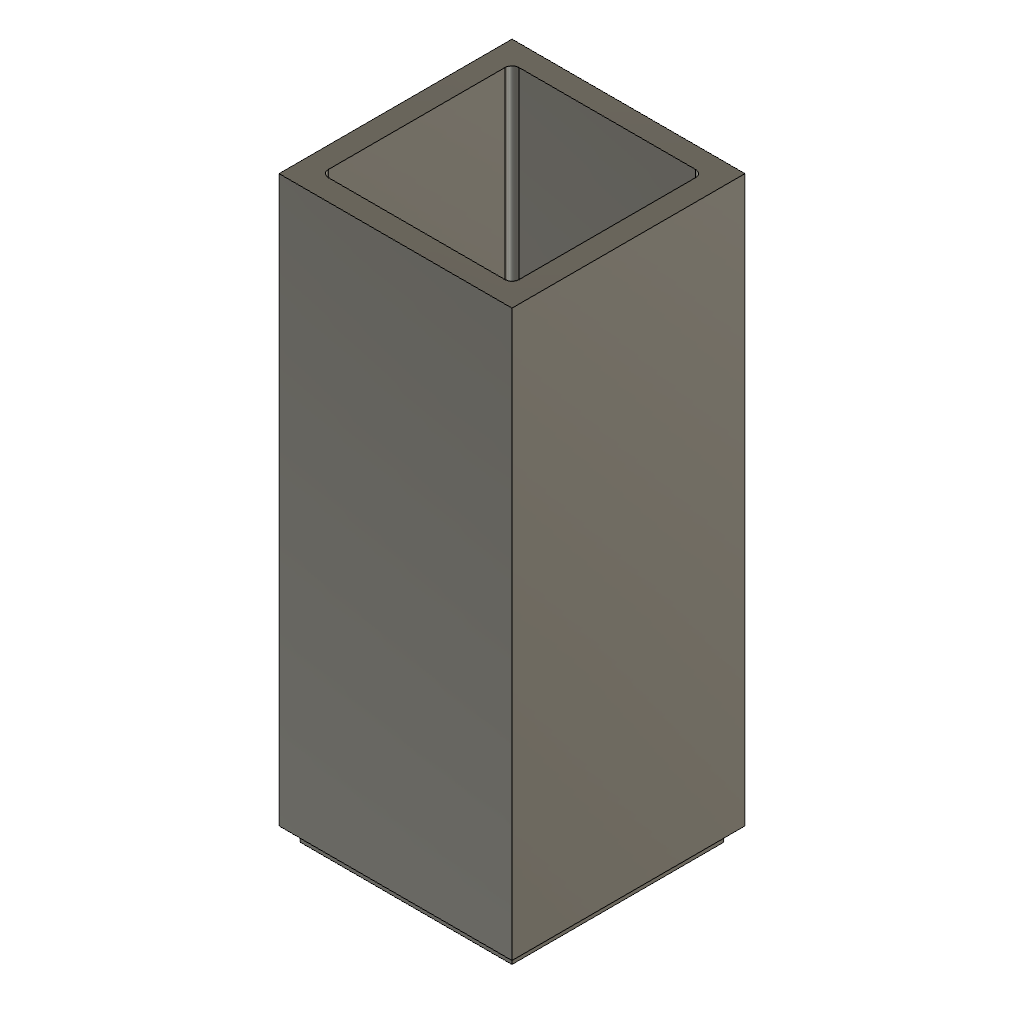
Single Compartment (Autodesk Fusion 360 design; units mm, degrees)
part number: 2026-10-19-01-48-57-490
Autodesk Fusion 360 part; units mm, degrees
sketch "Sketch1" plane through (0, 0, 0) normal (0, 0, 1) x (1, 0, 0)
  line L0 (7, 29.8327) -> (40, 29.8327)
  line L1 (40, 29.8327) -> (40, -3.1673)
  line L2 (40, -3.1673) -> (7, -3.1673)
  line L3 (7, -3.1673) -> (7, 29.8327)
  line L4 (10, 26.8327) -> (37, 26.8327)
  line L5 (37, 26.8327) -> (37, -0.1673)
  line L6 (37, -0.1673) -> (10, -0.1673)
  line L7 (10, -0.1673) -> (10, 26.8327)
  dimension "d1" = 3
  dimension "d2" = 3
  dimension "d3" = 3
  dimension "d4" = 3
  dimension "d5" = 33
  dimension "d6" = 33
  constraint horizontal L0
  constraint vertical L1
  constraint horizontal L2
  constraint vertical L3
  constraint horizontal L4
  constraint vertical L5
  constraint horizontal L6
  constraint vertical L7
  measures "d1" distance of L0 L4
  measures "d2" distance of L3 L7
  measures "d3" distance of L2 L6
  measures "d4" distance of L1 L5
  measures "d5" distance of L0 L2
  measures "d6" distance of L1 L3
extrude "Extrude1" add sketch "Sketch1" along normal blind 80
sketch "Sketch2" plane through (0, 0, 0) normal (0, 0, 1) x (1, 0, 0)
  line L0 (7.0843, -3.0828) -> (39.9602, -3.0828)
  line L1 (39.9602, -3.0828) -> (39.9602, 29.8087)
  line L2 (39.9602, 29.8087) -> (7.0843, 29.8087)
  line L3 (7.0843, 29.8087) -> (7.0843, -3.0828)
  constraint horizontal L0
  constraint vertical L1
  constraint horizontal L2
  constraint vertical L3
extrude "Extrude2" add sketch "Sketch2" along normal blind 3
sketch "Sketch3" plane through (0, 0, 0) normal (0, 0, 1) x (1, 0, 0)
  line L0 (7, -3.1675) -> (40, -3.1675)
  line L1 (40, -3.1675) -> (40, 29.8325)
  line L2 (40, 29.8325) -> (7, 29.8325)
  line L3 (7, 29.8325) -> (7, -3.1675)
  line L4 (8.5, -1.6675) -> (38.5, -1.6675)
  line L5 (38.5, -1.6675) -> (38.5, 28.3325)
  line L6 (38.5, 28.3325) -> (8.5, 28.3325)
  line L7 (8.5, 28.3325) -> (8.5, -1.6675)
  dimension "d11" = 33
  dimension "d12" = 33
  dimension "d13" = 1.5
  dimension "d14" = 1.5
  dimension "d15" = 1.5
  dimension "d16" = 1.5
  constraint horizontal L0
  constraint vertical L1
  constraint horizontal L2
  constraint vertical L3
  constraint horizontal L4
  constraint vertical L5
  constraint horizontal L6
  constraint vertical L7
  measures "d11" distance of L0 L2
  measures "d12" distance of L1 L3
  measures "d13" distance of L0 L4
  measures "d14" distance of L3 L7
  measures "d15" distance of L2 L6
  measures "d16" distance of L1 L5
extrude "Extrude3" add sketch "Sketch3" against normal blind 3 contours L4 L5 L6 L7
chamfer "Chamfer1" distance 1 angle 45 1 faces at (18.5, 18.3325, -3) tangent chain off
fillet "Fillet1" radius 1 1 edges at (10, 26.8327, 41.5)
fillet "Fillet2" radius 1 1 edges at (10, -0.1673, 41.5)
fillet "Fillet3" radius 1 1 edges at (37, -0.1673, 41.5)
fillet "Fillet4" radius 1 1 edges at (37, 26.8327, 41.5)
